Autodesk Inventor part; units mm, degrees
(part 2 of 2)
  arc A433 (25.5103, 19.3193) -> (25.5059, 19.4673) centre (25.405, 19.3903) ccw
  arc A434 (25.5059, 19.4673) -> (25.1988, 19.8633) centre (0, 0) ccw
  arc A435 (25.1988, 19.8633) -> (25.0565, 19.9043) centre (25.0991, 19.7847) ccw
  line L261 (25.0565, 19.9043) -> (24.6292, 19.7522)
  arc A436 (24.3483, 19.8295) -> (24.6292, 19.7522) centre (24.544, 19.9914) ccw
  line L262 (24.3483, 19.8295) -> (24.0407, 20.2013)
  arc A437 (24.0173, 20.4917) -> (24.0407, 20.2013) centre (24.2364, 20.3632) ccw
  line L263 (24.0173, 20.4917) -> (24.2469, 20.8829)
  arc A438 (24.2469, 20.8829) -> (24.2332, 21.0305) centre (24.1373, 20.9472) ccw
  arc A439 (24.2332, 21.0305) -> (23.9018, 21.4063) centre (0, 0) ccw
  arc A440 (23.9018, 21.4063) -> (23.7572, 21.4383) centre (23.8072, 21.3216) ccw
  line L264 (23.7572, 21.4383) -> (23.3403, 21.2597)
  arc A441 (23.0551, 21.3192) -> (23.3403, 21.2597) centre (23.2403, 21.4931) ccw
  line L265 (23.0551, 21.3192) -> (22.7248, 21.671)
  arc A442 (22.6833, 21.9594) -> (22.7248, 21.671) centre (22.91, 21.8448) ccw
  line L266 (22.6833, 21.9594) -> (22.8878, 22.3642)
  arc A443 (22.8878, 22.3642) -> (22.8649, 22.5106) centre (22.7744, 22.4215) ccw
  arc A444 (22.8649, 22.5106) -> (22.5106, 22.8649) centre (0, 0) ccw
  arc A445 (22.5106, 22.8649) -> (22.3642, 22.8878) centre (22.4215, 22.7744) ccw
  line L267 (22.3642, 22.8878) -> (21.9594, 22.6833)
  arc A446 (21.671, 22.7248) -> (21.9594, 22.6833) centre (21.8448, 22.91) ccw
  line L268 (21.671, 22.7248) -> (21.3192, 23.0551)
  arc A447 (21.2597, 23.3403) -> (21.3192, 23.0551) centre (21.4931, 23.2403) ccw
  line L269 (21.2597, 23.3403) -> (21.4383, 23.7572)
  arc A448 (21.4383, 23.7572) -> (21.4063, 23.9018) centre (21.3216, 23.8072) ccw
  arc A449 (21.4063, 23.9018) -> (21.0305, 24.2332) centre (0, 0) ccw
  arc A450 (21.0305, 24.2332) -> (20.8829, 24.2469) centre (20.9472, 24.1373) ccw
  line L270 (20.8829, 24.2469) -> (20.4917, 24.0173)
  arc A451 (20.2013, 24.0407) -> (20.4917, 24.0173) centre (20.3632, 24.2364) ccw
  line L271 (20.2013, 24.0407) -> (19.8295, 24.3483)
  arc A452 (19.7522, 24.6292) -> (19.8295, 24.3483) centre (19.9914, 24.544) ccw
  line L272 (19.7522, 24.6292) -> (19.9043, 25.0565)
  arc A453 (19.9043, 25.0565) -> (19.8633, 25.1988) centre (19.7847, 25.0991) ccw
  arc A454 (19.8633, 25.1988) -> (19.4673, 25.5059) centre (0, 0) ccw
  arc A455 (19.4673, 25.5059) -> (19.3193, 25.5103) centre (19.3903, 25.405) ccw
  line L273 (19.3193, 25.5103) -> (18.9432, 25.2566)
  arc A456 (18.6519, 25.2617) -> (18.9432, 25.2566) centre (18.8012, 25.4672) ccw
  line L274 (18.6519, 25.2617) -> (18.2616, 25.5453)
  arc A457 (18.1667, 25.8208) -> (18.2616, 25.5453) centre (18.4109, 25.7508) ccw
  line L275 (18.1667, 25.8208) -> (18.2917, 26.2568)
  arc A458 (18.2917, 26.2568) -> (18.2418, 26.3963) centre (18.1696, 26.2918) ccw
  arc A459 (18.2418, 26.3963) -> (17.8274, 26.678) centre (0, 0) ccw
  arc A460 (17.8274, 26.678) -> (17.6793, 26.673) centre (17.7568, 26.5724) ccw
  line L276 (17.6793, 26.673) -> (17.32, 26.3963)
  arc A461 (17.0289, 26.383) -> (17.32, 26.3963) centre (17.165, 26.5975) ccw
  line L277 (17.0289, 26.383) -> (16.6215, 26.6416)
  arc A462 (16.5096, 26.9106) -> (16.6215, 26.6416) centre (16.7576, 26.856) ccw
  line L278 (16.5096, 26.9106) -> (16.6069, 27.3536)
  arc A463 (16.6069, 27.3536) -> (16.5484, 27.4896) centre (16.4829, 27.3808) ccw
  arc A464 (16.5484, 27.4896) -> (16.1171, 27.7447) centre (0, 0) ccw
  arc A465 (16.1171, 27.7447) -> (15.9696, 27.7305) centre (16.0533, 27.6349) ccw
  line L279 (15.9696, 27.7305) -> (15.6284, 27.4317)
  arc A466 (15.3387, 27.4002) -> (15.6284, 27.4317) centre (15.4611, 27.6228) ccw
  line L280 (15.3387, 27.4002) -> (14.9159, 27.6327)
  arc A467 (14.7872, 27.8941) -> (14.9159, 27.6327) centre (15.0383, 27.8553) ccw
  line L281 (14.7872, 27.8941) -> (14.8566, 28.3423)
  arc A468 (14.8566, 28.3423) -> (14.7897, 28.4745) centre (14.7311, 28.3618) ccw
  arc A469 (14.7897, 28.4745) -> (14.3432, 28.702) centre (0, 0) ccw
  arc A470 (14.3432, 28.702) -> (14.1969, 28.6785) centre (14.2864, 28.5884) ccw
  line L282 (14.1969, 28.6785) -> (13.8751, 28.3589)
  arc A471 (13.588, 28.3093) -> (13.8751, 28.3589) centre (13.6961, 28.5391) ccw
  line L283 (13.588, 28.3093) -> (13.1514, 28.5147)
  arc A472 (13.0066, 28.7676) -> (13.1514, 28.5147) centre (13.2595, 28.7446) ccw
  line L284 (13.0066, 28.7676) -> (13.0477, 29.2193)
  arc A473 (13.0477, 29.2193) -> (12.9726, 29.3469) centre (12.9212, 29.2308) ccw
  arc A474 (12.9726, 29.3469) -> (12.5127, 29.5459) centre (0, 0) ccw
  arc A475 (12.5127, 29.5459) -> (12.3682, 29.5133) centre (12.4631, 29.429) ccw
  line L285 (12.3682, 29.5133) -> (12.067, 29.1741)
  arc A476 (11.7836, 29.1066) -> (12.067, 29.1741) centre (11.8771, 29.3428) ccw
  line L286 (11.7836, 29.1066) -> (11.335, 29.2842)
  arc A477 (11.1746, 29.5275) -> (11.335, 29.2842) centre (11.4285, 29.5204) ccw
  line L287 (11.1746, 29.5275) -> (11.1872, 29.9809)
  arc A478 (11.1872, 29.9809) -> (11.1043, 30.1036) centre (11.0603, 29.9844) ccw
  arc A479 (11.1043, 30.1036) -> (10.6328, 30.2733) centre (0, 0) ccw
  arc A480 (10.6328, 30.2733) -> (10.4906, 30.2317) centre (10.5907, 30.1535) ccw
  line L288 (10.4906, 30.2317) -> (10.2114, 29.8743)
  arc A481 (9.9327, 29.7891) -> (10.2114, 29.8743) centre (10.0112, 30.0307) ccw
  line L289 (9.9327, 29.7891) -> (9.4738, 29.9382)
  arc A482 (9.2985, 30.1709) -> (9.4738, 29.9382) centre (9.5523, 30.1798) ccw
  line L290 (9.2985, 30.1709) -> (9.2827, 30.6242)
  arc A483 (9.2827, 30.6242) -> (9.1921, 30.7414) centre (9.1557, 30.6197) ccw
  arc A484 (9.1921, 30.7414) -> (8.7109, 30.8812) centre (0, 0) ccw
  arc A485 (8.7109, 30.8812) -> (8.5716, 30.8307) centre (8.6764, 30.759) ccw
  line L291 (8.5716, 30.8307) -> (8.3154, 30.4565)
  arc A486 (8.0427, 30.354) -> (8.3154, 30.4565) centre (8.1058, 30.6) ccw
  line L292 (8.0427, 30.354) -> (7.5753, 30.474)
  arc A487 (7.3857, 30.6952) -> (7.5753, 30.474) centre (7.6385, 30.72) ccw
  line L293 (7.3857, 30.6952) -> (7.3414, 31.1466)
  arc A488 (7.3414, 31.1466) -> (7.2437, 31.2579) centre (7.215, 31.1342) ccw
  arc A489 (7.2437, 31.2579) -> (6.7547, 31.3672) centre (0, 0) ccw
  arc A490 (6.7547, 31.3672) -> (6.6188, 31.3081) centre (6.7279, 31.2431) ccw
  line L294 (6.6188, 31.3081) -> (6.3866, 30.9185)
  arc A491 (6.1208, 30.7991) -> (6.3866, 30.9185) centre (6.1684, 31.0486) ccw
  line L295 (6.1208, 30.7991) -> (5.6469, 30.8895)
  arc A492 (5.4438, 31.0984) -> (5.6469, 30.8895) centre (5.6945, 31.139) ccw
  line L296 (5.4438, 31.0984) -> (5.3712, 31.5461)
  arc A493 (5.3712, 31.5461) -> (5.2667, 31.6511) centre (5.2459, 31.5258) ccw
  arc A494 (5.2667, 31.6511) -> (4.7718, 31.7295) centre (0, 0) ccw
  arc A495 (4.7718, 31.7295) -> (4.6399, 31.6619) centre (4.7529, 31.6039) ccw
  line L297 (4.6399, 31.6619) -> (4.4326, 31.2585)
  arc A496 (4.1749, 31.1226) -> (4.4326, 31.2585) centre (4.2067, 31.3746) ccw
  line L298 (4.1749, 31.1226) -> (3.6962, 31.1831)
  arc A497 (3.4803, 31.3788) -> (3.6962, 31.1831) centre (3.728, 31.4351) ccw
  line L299 (3.4803, 31.3788) -> (3.3798, 31.8211)
  arc A498 (3.3798, 31.8211) -> (3.2689, 31.9193) centre (3.256, 31.793) ccw
  arc A499 (3.2689, 31.9193) -> (2.7701, 31.9665) centre (0, 0) ccw
  circle A500 centre (0, 0) radius 35
  point P0 (0, 0)
  point P1 (4.6399, 31.6619)
  point P2 (4.7718, 31.7295)
  point P3 (6.7547, 31.3672)
  point P4 (7.2437, 31.2579)
  point P5 (8.5716, 30.8307)
  point P6 (8.7109, 30.8812)
  point P7 (9.1921, 30.7414)
  point P8 (10.6328, 30.2733)
  point P9 (11.1043, 30.1036)
  point P10 (12.5127, 29.5459)
  point P11 (12.9726, 29.3469)
  point P12 (13.588, 28.3093)
  point P13 (14.1969, 28.6785)
  point P14 (14.3432, 28.702)
  point P15 (14.7897, 28.4745)
  point P16 (15.9696, 27.7305)
  point P17 (16.1171, 27.7447)
  point P18 (17.0289, 26.383)
  point P19 (17.6793, 26.673)
  point P20 (17.8274, 26.678)
  point P21 (18.1667, 25.8208)
  point P22 (21.4063, 23.9018)
  point P23 (21.2597, 23.3403)
  point P24 (22.3642, 22.8878)
  point P25 (22.5106, 22.8649)
  point P26 (22.8649, 22.5106)
  point P27 (23.9018, 21.4063)
  point P28 (24.2332, 21.0305)
  point P29 (24.0173, 20.4917)
  point P30 (24.3483, 19.8295)
  point P31 (25.0565, 19.9043)
  point P32 (25.1988, 19.8633)
  point P33 (25.5059, 19.4673)
  point P34 (26.3963, 18.2418)
  point P35 (27.4896, 16.5484)
  point P36 (27.7447, 16.1171)
  point P37 (28.4745, 14.7897)
  point P38 (28.702, 14.3432)
  point P39 (28.5147, 13.1514)
  point P40 (29.3469, 12.9726)
  point P41 (29.5459, 12.5127)
  point P42 (30.1036, 11.1043)
  point P43 (30.7414, 9.1921)
  point P44 (31.2579, 7.2437)
  point P45 (31.3672, 6.7547)
  point P46 (30.9185, 6.3866)
  point P47 (31.6511, 5.2667)
  point P48 (31.7295, 4.7718)
  point P49 (31.2585, 4.4326)
  point P50 (31.8211, 3.3798)
  point P51 (31.9193, 3.2689)
  point P52 (31.9665, 2.7701)
  point P53 (31.4752, 2.4611)
  point P54 (31.3537, 1.7309)
  point P55 (31.9706, 1.3751)
  point P56 (32.0616, 1.2583)
  point P57 (31.5676, 0.4799)
  point P58 (31.4005, 0.2412)
  point P59 (31.4005, -0.2412)
  point P60 (31.9938, -0.6351)
  point P61 (32.0773, -0.7574)
  point P62 (31.5355, -1.5032)
  point P63 (31.8908, -2.6427)
  point P64 (31.9665, -2.7701)
  point P65 (31.3788, -3.4803)
  point P66 (31.6619, -4.6399)
  point P67 (31.7295, -4.7718)
  point P68 (31.3081, -6.6188)
  point P69 (31.3672, -6.7547)
  point P70 (31.2579, -7.2437)
  point P71 (30.354, -8.0427)
  point P72 (30.8812, -8.7109)
  point P73 (30.7414, -9.1921)
  point P74 (30.2733, -10.6328)
  point P75 (30.1036, -11.1043)
  point P76 (29.5459, -12.5127)
  point P77 (29.3469, -12.9726)
  point P78 (28.3093, -13.588)
  point P79 (28.702, -14.3432)
  point P80 (28.4745, -14.7897)
  point P81 (27.7305, -15.9696)
  point P82 (27.7447, -16.1171)
  point P83 (26.678, -17.8274)
  point P84 (26.3963, -18.2418)
  point P85 (25.8208, -18.1667)
  point P86 (25.5059, -19.4673)
  point P87 (25.1988, -19.8633)
  point P88 (24.2469, -20.8829)
  point P89 (24.2332, -21.0305)
  point P90 (22.8649, -22.5106)
  point P91 (22.5106, -22.8649)
  point P92 (21.9594, -22.6833)
  point P93 (21.4063, -23.9018)
  point P94 (21.0305, -24.2332)
  point P95 (20.4917, -24.0173)
  point P96 (19.8633, -25.1988)
  point P97 (18.2917, -26.2568)
  point P98 (18.2418, -26.3963)
  point P99 (17.8274, -26.678)
  point P100 (16.5484, -27.4896)
  point P101 (16.1171, -27.7447)
  point P102 (15.6284, -27.4317)
  point P103 (14.7897, -28.4745)
  point P104 (14.3432, -28.702)
  point P105 (13.8751, -28.3589)
  point P106 (13.0477, -29.2193)
  point P107 (12.9726, -29.3469)
  point P108 (11.335, -29.2842)
  point P109 (11.1872, -29.9809)
  point P110 (11.1043, -30.1036)
  point P111 (10.6328, -30.2733)
  point P112 (10.2114, -29.8743)
  point P113 (9.4738, -29.9382)
  point P114 (9.1921, -30.7414)
  point P115 (7.5753, -30.474)
  point P116 (7.2437, -31.2579)
  point P117 (5.2667, -31.6511)
  point P118 (4.7718, -31.7295)
  point P119 (4.4326, -31.2585)
  point P120 (3.3798, -31.8211)
  point P121 (3.2689, -31.9193)
  point P122 (2.7701, -31.9665)
  point P123 (2.4611, -31.4752)
  point P124 (1.2583, -32.0616)
  point P125 (0.7574, -32.0773)
  point P126 (0.4799, -31.5676)
  point P127 (-0.2412, -31.4005)
  point P128 (-0.6351, -31.9938)
  point P129 (-0.7574, -32.0773)
  point P130 (-1.5032, -31.5355)
  point P131 (-2.6427, -31.8908)
  point P132 (-2.7701, -31.9665)
  point P133 (-3.4803, -31.3788)
  point P134 (-4.6399, -31.6619)
  point P135 (-4.7718, -31.7295)
  point P136 (-6.6188, -31.3081)
  point P137 (-6.7547, -31.3672)
  point P138 (-7.3857, -30.6952)
  point P139 (-8.0427, -30.354)
  point P140 (-8.7109, -30.8812)
  point P141 (-10.4906, -30.2317)
  point P142 (-10.6328, -30.2733)
  point P143 (-11.7836, -29.1066)
  point P144 (-12.5127, -29.5459)
  point P145 (-14.3432, -28.702)
  point P146 (-14.7897, -28.4745)
  point P147 (-15.3387, -27.4002)
  point P148 (-16.1171, -27.7447)
  point P149 (-17.0289, -26.383)
  point P150 (-17.6793, -26.673)
  point P151 (-17.8274, -26.678)
  point P152 (-18.2418, -26.3963)
  point P153 (-19.4673, -25.5059)
  point P154 (-20.8829, -24.2469)
  point P155 (-21.0305, -24.2332)
  point P156 (-21.2597, -23.3403)
  point P157 (-22.3642, -22.8878)
  point P158 (-22.5106, -22.8649)
  point P159 (-23.9018, -21.4063)
  point P160 (-24.3483, -19.8295)
  point P161 (-25.1988, -19.8633)
  point P162 (-25.2566, -18.9432)
  point P163 (-26.3963, -18.2418)
  point P164 (-26.678, -17.8274)
  point P165 (-27.4896, -16.5484)
  point P166 (-27.7447, -16.1171)
  point P167 (-27.4317, -15.6284)
  point P168 (-28.4745, -14.7897)
  point P169 (-28.702, -14.3432)
  point P170 (-29.3469, -12.9726)
  point P171 (-30.1036, -11.1043)
  point P172 (-30.2733, -10.6328)
  point P173 (-29.8743, -10.2114)
  point P174 (-29.9382, -9.4738)
  point P175 (-30.7414, -9.1921)
  point P176 (-30.8812, -8.7109)
  point P177 (-30.474, -7.5753)
  point P178 (-31.2579, -7.2437)
  point P179 (-31.3672, -6.7547)
  point P180 (-31.5461, -5.3712)
  point P181 (-31.6511, -5.2667)
  point P182 (-31.7295, -4.7718)
  point P183 (-31.8211, -3.3798)
  point P184 (-31.9193, -3.2689)
  point P185 (-31.9665, -2.7701)
  point P186 (-31.4752, -2.4611)
  point P187 (-31.3537, -1.7309)
  point P188 (-31.9706, -1.3751)
  point P189 (-32.0616, -1.2583)
  point P190 (-31.5676, -0.4799)
  point P191 (-31.9938, 0.6351)
  point P192 (-32.0773, 0.7574)
  point P193 (-32.0616, 1.2583)
  point P194 (-31.5355, 1.5032)
  point P195 (-31.8908, 2.6427)
  point P196 (-31.9665, 2.7701)
  point P197 (-31.6619, 4.6399)
  point P198 (-31.7295, 4.7718)
  point P199 (-31.3672, 6.7547)
  dimension "d0" = 70
  constraints: 1000 point on circle, 600 end point, 501 centre point, 1 coincident
  measures "d0" diameter of A500
extrude "押し出し1" add sketch "スケッチ1" along normal mid plane 7
